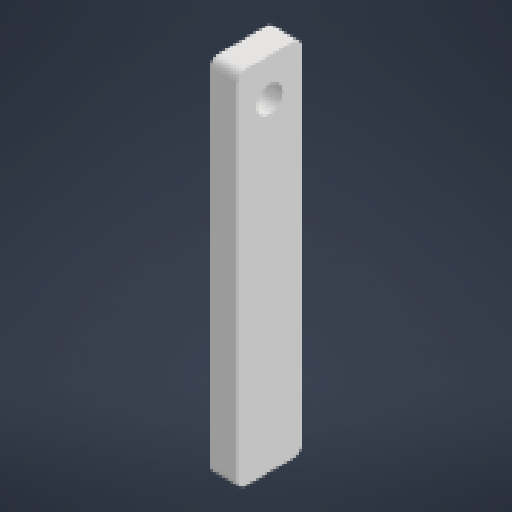
# Autodesk Inventor part: reposecarte
Saved by Autodesk Inventor 2026.1 (Build 301233020, 233B)
## iProperties
Created: 2025-12-03
Part Number: reposecarte
Material: Générique
Document SubType Name: Modeling
Designer: matpo
Density: 1 g/cm^3
Appearance: Par défaut
Author: matpo
Autodesk Inventor part; units mm, degrees
ref_plane "YZ Plane" through (0, 0, 0) normal (1, 0, 0) x (0, 1, 0)
ref_plane "XZ Plane" through (0, 0, 0) normal (0, 1, 0) x (-1, 0, 0)
ref_plane "XY Plane" through (0, 0, 0) normal (0, 0, 1) x (1, 0, 0)
sketch "Esquisse1" plane through (0, 0, 0) normal (0, 0, 1) x (1, 0, 0)
  line L0 (-9.2629, 23) -> (-9.2629, -22.9536) projected
  line L1 (-9.2629, -22.9536) -> (-5.9004, -22.9536) projected
  line L2 (-5.9004, -22.9536) -> (-5.9004, 23) projected
  line L3 (-5.9004, 23) -> (-8.0764, 23) projected
  line L4 (-9.2629, 23) -> (-9.2629, -22.9536) projected
  line L5 (-5.9004, 23) -> (-9.2629, 23) projected
  line L6 (-5.9004, 22) -> (-9.2629, 22)
  point P0 (0, 0)
  dimension "d9" = 1
  constraints: 2 end point, 2 point on line, 1 perpendicular
  measures "d9" distance between parallel lines of L3 L6
extrude "Extrusion1" add sketch "Esquisse1" along normal mid plane 8 contours L6 L2 L1 L0
sketch "Esquisse2" plane through (-9.2629, -22.9536, 4) normal (-1, 0, 0) x (0, 0, 1)
  circle A0 centre (-4, 40.2044) radius 1.95 projected
  point P0 (-4, 22.9536)
hole "Perçage1" at (-9.2629, 17.2508, 0) direction (1, 0, 0) diameter 3.2 depth 8 counterbore diameter 6.2 counterbore depth 1
fillet "Congé1" radius 1 4 edges at (-7.5816, 22, 4) (-7.5816, 22, -4) (-7.5816, -22.9536, 4) (-7.5816, -22.9536, -4)
